CardHolder (Autodesk Fusion 360 design; units mm, degrees)
Autodesk Fusion 360 part; units mm, degrees
sketch "Sketch1" plane through (0, 0, 0) normal (0, 1, 0) x (1, 0, 0)
  line L0 (25.5, 44.5) -> (-25.5, 44.5)
  line L1 (-25.5, 44.5) -> (-25.5, -44.5)
  line L2 (-25.5, -44.5) -> (25.5, -44.5)
  line L3 (25.5, -44.5) -> (25.5, 44.5)
  line L4 (25.5, 44.5) -> (-25.5, -44.5) construction
  line L5 (-25.5, 44.5) -> (25.5, -44.5) construction
  dimension "d1" = 51
  dimension "d2" = 89
  constraint perpendicular L0 L1
  constraint parallel L0 L2
  constraint parallel L1 L3
  constraint horizontal L0
  constraint coincident L4 origin
  constraint coincident L5 origin
  measures "d1" distance of L1.end L2.end
  measures "d2" distance of L0.end L1.end
extrude "Extrude1" add sketch "Sketch1" along normal blind 10 makes body 1
sketch "Sketch2" plane through (0, 0, 44.5) normal (0, 0, 1) x (1, 0, 0)
  line L0 (-25.5, 0) -> (25.5, 0)
  line L1 (25.5, 0) -> (25.5, 10)
  line L2 (25.5, 10) -> (-25.5, 10)
  line L3 (-25.5, 10) -> (-25.5, 0)
  line L4 (27.1, -1.6) -> (-27.1, -1.6)
  line L5 (-27.1, -1.6) -> (-27.1, 11.6)
  line L6 (-27.1, 11.6) -> (27.1, 11.6)
  line L7 (27.1, 11.6) -> (27.1, -1.6)
  line L8 (27.1, -1.6) -> (-27.1, 11.6) construction
  line L9 (-27.1, -1.6) -> (27.1, 11.6) construction
  point P0 (0, 5)
  dimension "d5" = 54.2
  dimension "d6" = 13.2
  constraint perpendicular L4 L5
  constraint parallel L4 L6
  constraint parallel L5 L7
  constraint horizontal L4
  constraint coincident L8 P0
  constraint coincident L9 P0
  measures "d5" distance of L5.end L6.end
  measures "d6" distance of L4.end L5.end
extrude "Extrude2" add sketch "Sketch2" along normal blind 1.4 separate body contours L0 L1 L2 L3 | L4 L5 L6 L7 makes body 2
sketch "Sketch3" plane through (0, 0, 44.5) normal (0, 0, -1) x (-1, 0, 0)
  line L0 (27.1, 11.6) -> (-27.1, 11.6)
  line L1 (-27.1, 11.6) -> (-27.1, -1.6)
  line L2 (-27.1, -1.6) -> (27.1, -1.6)
  line L3 (27.1, -1.6) -> (27.1, 11.6)
  line L4 (25.5, 0) -> (-25.5, 0)
  line L5 (-25.5, 0) -> (-25.5, 10)
  line L6 (-25.5, 10) -> (25.5, 10)
  line L7 (25.5, 10) -> (25.5, 0)
  line L8 (25.5, 0) -> (-25.5, 10) construction
  line L9 (-25.5, 0) -> (25.5, 10) construction
  point P0 (0, 5)
  point P1 (25.5, 0)
  constraint perpendicular L4 L5
  constraint parallel L4 L6
  constraint parallel L5 L7
  constraint horizontal L4
  constraint coincident P1 L4.start
  constraint coincident L8 P0
  constraint coincident L9 P0
extrude "Extrude3" add sketch "Sketch3" along normal blind 50 separate body makes body 3
combine "Combine1" operation add target body 3 tool bodies 2
sketch "Sketch4" plane through (0, 11.6, 0) normal (0, 1, 0) x (-1, 0, 0)
  line L0 (-27.1, 45.9) -> (-27.1, -5.5)
  line L1 (-27.1, -5.5) -> (27.1, -5.5)
  line L2 (27.1, -5.5) -> (27.1, 45.9)
  line L3 (27.1, 45.9) -> (-27.1, 45.9)
  line L4 (27.1, -5.5) -> (25.5, -5.5)
  line L5 (25.5, -5.5) -> (-27.1, 20.2)
  dimension "d11" = 1.6
  constraint coincident L1.end L2.start
  constraint perpendicular L2 L4
  constraint midpoint L0 L5.end
  measures "d11" distance of L1.end L4.end
extrude "Extrude4" cut sketch "Sketch4" against normal blind 13.2 contours L0 L1 L5 bodies 3
hidden bodies 1
